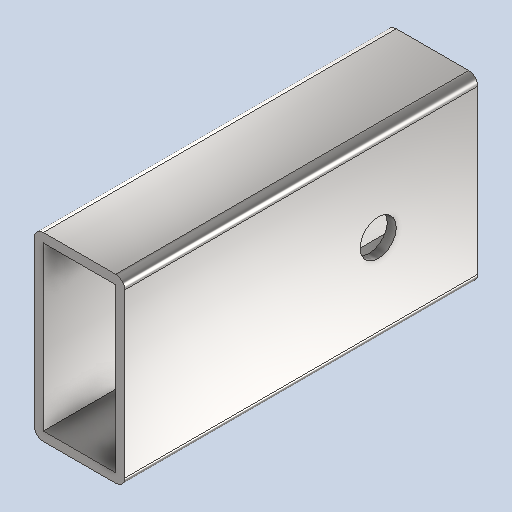
# Autodesk Inventor part: Anschweißlasche
Saved by Autodesk Inventor 2026.2 (Build 302298010, 298A)
## iProperties
Created: 2026-07-28
Part Number: Anschweißlasche
Material: Stahl, Kohlenstoff
Document SubType Name: Modeling
Designer: moest
Density: 7.85 g/cm^3
Appearance: Halbpoliert
Author: moest
Autodesk Inventor part; units mm, degrees
ref_plane "YZ Plane" through (0, 0, 0) normal (1, 0, 0) x (0, 1, 0)
ref_plane "XZ Plane" through (0, 0, 0) normal (0, 1, 0) x (-1, 0, 0)
ref_plane "XY Plane" through (0, 0, 0) normal (0, 0, 1) x (1, 0, 0)
sketch "Skizze1" plane through (0, 0, 0) normal (0, 1, 0) x (-1, 0, 0)
  line L0 (0, 0) -> (20, 0)
  line L1 (20, 0) -> (20, -40)
  line L2 (20, -40) -> (0, -40)
  line L3 (0, -40) -> (0, 0)
  line L4 (2, -2) -> (18, -2)
  line L5 (18, -2) -> (18, -38)
  line L6 (18, -38) -> (2, -38)
  line L7 (2, -38) -> (2, -2)
  dimension "d0" = 20
  dimension "d1" = 40
  dimension "d2" = 2
  dimension "d3" = 2
  dimension "d4" = 2
  dimension "d5" = 2
  constraints: 16 end point, 4 parallel, 2 horizontal, 2 perpendicular
  measures "d0" distance of L1.end L2.end
  measures "d1" distance between parallel lines of L2 L0
  measures "d2" distance between parallel lines of L0 L4
  measures "d3" distance between parallel lines of L1 L5
  measures "d4" distance between parallel lines of L2 L6
  measures "d5" distance between parallel lines of L3 L7
extrude "Extrusion1" add sketch "Skizze1" along normal blind 78
fillet "Rundung1" radius 2 4 edges at (-20, 39, -40) (0, 39, -40) (0, 39, 0) (-20, 39, 0)
sketch "Skizze2" plane through (-20, 0, -38) normal (-1, 0, 0) x (0, 0, 1)
  line L0 (38, 0) -> (38, 78) projected
  line L1 (0, 78) -> (36, 78) projected
  circle A0 centre (18, 56) radius 4
  dimension "d9" = 20
  dimension "d10" = 22
  dimension "d11" = 8
  constraints: 1 centre point, 1 coincident
  measures "d9" distance from line of L0 point (18, 56)
  measures "d10" distance from line of L1 point (18, 56)
  measures "d11" diameter of A0
extrude "Extrusion2" cut sketch "Skizze2" against normal blind 78
